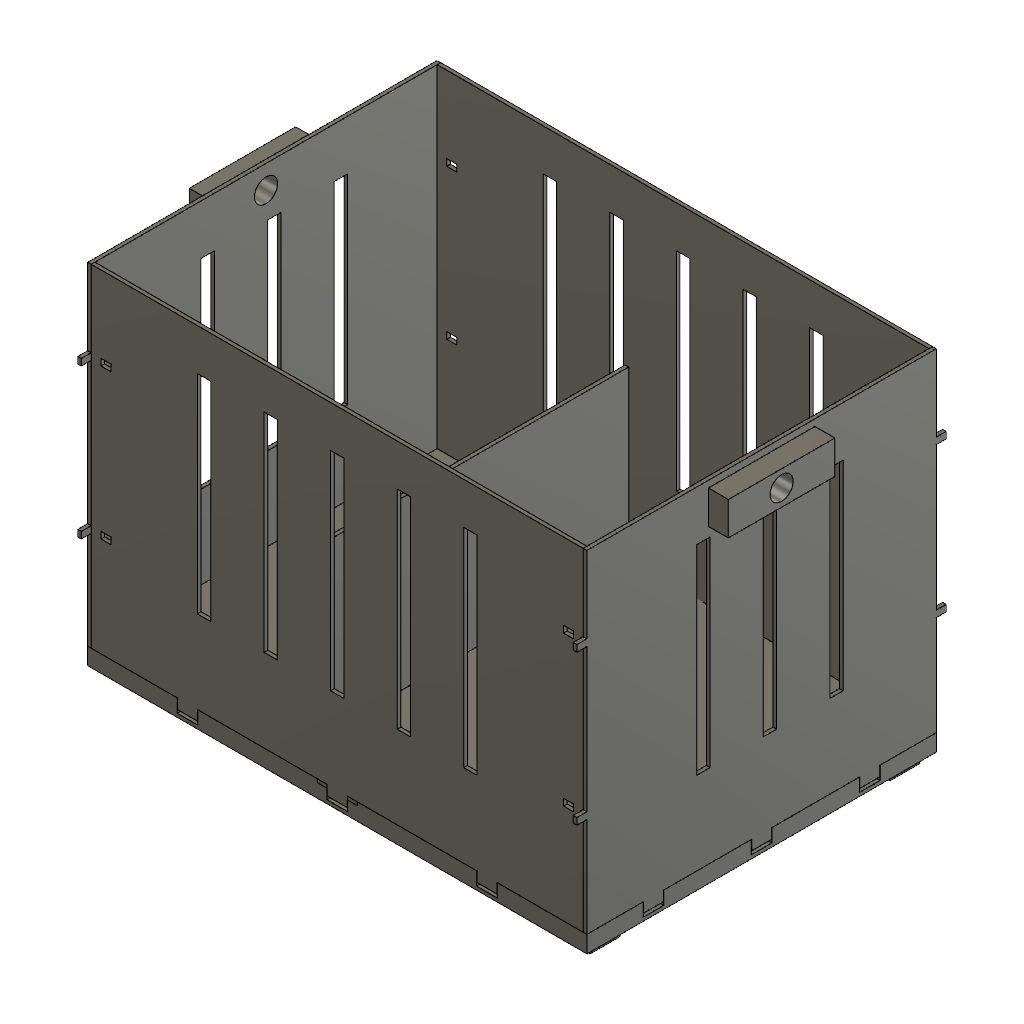
snapbox_5part (Autodesk Fusion 360 design; units mm, degrees)
part number: 2026-11-01-21-20-34-892
Autodesk Fusion 360 part; units mm, degrees
sketch "草图31" plane through (0, 0, 0) normal (0, 0, 1) x (1, 0, 0)
  line L0 (0, 0) -> (260, 0)
  line L1 (260, 0) -> (260, 180)
  line L2 (260, 180) -> (0, 180)
  line L3 (0, 180) -> (0, 0)
ref_plane "工作平面25" through (0, 0, 2.2) normal (0, 0, 1) x (1, 0, 0)
sketch "草图32" plane through (0, 0, 2.2) normal (0, 0, 1) x (1, 0, 0)
  line L0 (0, 0) -> (2.2, 0)
  line L1 (2.2, 0) -> (2.2, 180)
  line L2 (2.2, 180) -> (0, 180)
  line L3 (0, 180) -> (0, 0)
  line L4 (257.8, 0) -> (260, 0)
  line L5 (260, 0) -> (260, 180)
  line L6 (260, 180) -> (257.8, 180)
  line L7 (257.8, 180) -> (257.8, 0)
  line L8 (2.2, 0) -> (257.8, 0)
  line L9 (257.8, 0) -> (257.8, 2.2)
  line L10 (257.8, 2.2) -> (2.2, 2.2)
  line L11 (2.2, 2.2) -> (2.2, 0)
  line L12 (2.2, 177.8) -> (257.8, 177.8)
  line L13 (257.8, 177.8) -> (257.8, 180)
  line L14 (257.8, 180) -> (2.2, 180)
  line L15 (2.2, 180) -> (2.2, 177.8)
ref_plane "工作平面26" through (0, 0, -5) normal (0, 0, 1) x (1, 0, 0)
sketch "草图33" plane through (0, 0, -5) normal (0, 0, 1) x (1, 0, 0)
  line L0 (4, 6) -> (40, 6)
  line L1 (40, 6) -> (40, 24)
  line L2 (40, 24) -> (4, 24)
  line L3 (4, 24) -> (4, 6)
  line L4 (4, 156) -> (40, 156)
  line L5 (40, 156) -> (40, 174)
  line L6 (40, 174) -> (4, 174)
  line L7 (4, 174) -> (4, 156)
  line L8 (220, 6) -> (256, 6)
  line L9 (256, 6) -> (256, 24)
  line L10 (256, 24) -> (220, 24)
  line L11 (220, 24) -> (220, 6)
  line L12 (220, 156) -> (256, 156)
  line L13 (256, 156) -> (256, 174)
  line L14 (256, 174) -> (220, 174)
  line L15 (220, 174) -> (220, 156)
ref_plane "工作平面27" through (0, 0, 2.2) normal (0, 0, 1) x (1, 0, 0)
sketch "草图34" plane through (0, 0, 2.2) normal (0, 0, 1) x (1, 0, 0)
  line L0 (0, 23.8) -> (2.2, 23.8)
  line L1 (2.2, 23.8) -> (2.2, 36.2)
  line L2 (2.2, 36.2) -> (0, 36.2)
  line L3 (0, 36.2) -> (0, 23.8)
  line L4 (257.8, 23.8) -> (260, 23.8)
  line L5 (260, 23.8) -> (260, 36.2)
  line L6 (260, 36.2) -> (257.8, 36.2)
  line L7 (257.8, 36.2) -> (257.8, 23.8)
  line L8 (0, 83.8) -> (2.2, 83.8)
  line L9 (2.2, 83.8) -> (2.2, 96.2)
  line L10 (2.2, 96.2) -> (0, 96.2)
  line L11 (0, 96.2) -> (0, 83.8)
  line L12 (257.8, 83.8) -> (260, 83.8)
  line L13 (260, 83.8) -> (260, 96.2)
  line L14 (260, 96.2) -> (257.8, 96.2)
  line L15 (257.8, 96.2) -> (257.8, 83.8)
  line L16 (0, 143.8) -> (2.2, 143.8)
  line L17 (2.2, 143.8) -> (2.2, 156.2)
  line L18 (2.2, 156.2) -> (0, 156.2)
  line L19 (0, 156.2) -> (0, 143.8)
  line L20 (257.8, 143.8) -> (260, 143.8)
  line L21 (260, 143.8) -> (260, 156.2)
  line L22 (260, 156.2) -> (257.8, 156.2)
  line L23 (257.8, 156.2) -> (257.8, 143.8)
  line L24 (43.8, 0) -> (56.2, 0)
  line L25 (56.2, 0) -> (56.2, 2.2)
  line L26 (56.2, 2.2) -> (43.8, 2.2)
  line L27 (43.8, 2.2) -> (43.8, 0)
  line L28 (43.8, 177.8) -> (56.2, 177.8)
  line L29 (56.2, 177.8) -> (56.2, 180)
  line L30 (56.2, 180) -> (43.8, 180)
  line L31 (43.8, 180) -> (43.8, 177.8)
  line L32 (123.8, 0) -> (136.2, 0)
  line L33 (136.2, 0) -> (136.2, 2.2)
  line L34 (136.2, 2.2) -> (123.8, 2.2)
  line L35 (123.8, 2.2) -> (123.8, 0)
  line L36 (123.8, 177.8) -> (136.2, 177.8)
  line L37 (136.2, 177.8) -> (136.2, 180)
  line L38 (136.2, 180) -> (123.8, 180)
  line L39 (123.8, 180) -> (123.8, 177.8)
  line L40 (203.8, 0) -> (216.2, 0)
  line L41 (216.2, 0) -> (216.2, 2.2)
  line L42 (216.2, 2.2) -> (203.8, 2.2)
  line L43 (203.8, 2.2) -> (203.8, 0)
  line L44 (203.8, 177.8) -> (216.2, 177.8)
  line L45 (216.2, 177.8) -> (216.2, 180)
  line L46 (216.2, 180) -> (203.8, 180)
  line L47 (203.8, 180) -> (203.8, 177.8)
sketch "草图35" plane through (0, 0, 0) normal (1, 0, 0) x (0, 0, -1)
  line L0 (-10.2, 0) -> (-10.2, 180)
  line L1 (-10.2, 180) -> (-160, 180)
  line L2 (-160, 180) -> (-160, 0)
  line L3 (-160, 0) -> (-10.2, 0)
  line L4 (-4.2, 24) -> (-4.2, 36)
  line L5 (-4.2, 36) -> (-10.2, 36)
  line L6 (-10.2, 36) -> (-10.2, 24)
  line L7 (-10.2, 24) -> (-4.2, 24)
  line L8 (-4.2, 84) -> (-4.2, 96)
  line L9 (-4.2, 96) -> (-10.2, 96)
  line L10 (-10.2, 96) -> (-10.2, 84)
  line L11 (-10.2, 84) -> (-4.2, 84)
  line L12 (-4.2, 144) -> (-4.2, 156)
  line L13 (-4.2, 156) -> (-10.2, 156)
  line L14 (-10.2, 156) -> (-10.2, 144)
  line L15 (-10.2, 144) -> (-4.2, 144)
sketch "草图36" plane through (0, 0, 0) normal (1, 0, 0) x (0, 0, -1)
  line L0 (-48, -6) -> (-48, 1)
  line L1 (-48, 1) -> (-52, 1)
  line L2 (-52, 1) -> (-52, -6)
  line L3 (-52, -6) -> (-48, -6)
  line L4 (-48, 179) -> (-48, 186)
  line L5 (-48, 186) -> (-52, 186)
  line L6 (-52, 186) -> (-52, 179)
  line L7 (-52, 179) -> (-48, 179)
  line L8 (-118, -6) -> (-118, 1)
  line L9 (-118, 1) -> (-122, 1)
  line L10 (-122, 1) -> (-122, -6)
  line L11 (-122, -6) -> (-118, -6)
  line L12 (-118, 179) -> (-118, 186)
  line L13 (-118, 186) -> (-122, 186)
  line L14 (-122, 186) -> (-122, 179)
  line L15 (-122, 179) -> (-118, 179)
ref_plane "工作平面28" through (0, 0, 136) normal (0, 0, 1) x (1, 0, 0)
sketch "草图37" plane through (0, 0, 136) normal (0, 0, 1) x (1, 0, 0)
  line L0 (-12, 58) -> (1, 58)
  line L1 (1, 58) -> (1, 122)
  line L2 (1, 122) -> (-12, 122)
  line L3 (-12, 122) -> (-12, 58)
ref_plane "工作平面29" through (1.1, 0, 0) normal (1, 0, 0) x (0, 1, 0)
sketch "草图38" plane through (1.1, 0, 0) normal (1, 0, 0) x (0, 0, -1)
  circle A0 through (-138, 90, -1.1) (-148.5, 96.0622, -1.1) (-148.5, 83.9378, -1.1)
ref_plane "工作平面30" through (257.8, 0, 0) normal (1, 0, 0) x (0, 1, 0)
sketch "草图39" plane through (257.8, 0, 0) normal (1, 0, 0) x (0, 0, -1)
  line L0 (-10.2, 0) -> (-10.2, 180)
  line L1 (-10.2, 180) -> (-160, 180)
  line L2 (-160, 180) -> (-160, 0)
  line L3 (-160, 0) -> (-10.2, 0)
  line L4 (-4.2, 24) -> (-4.2, 36)
  line L5 (-4.2, 36) -> (-10.2, 36)
  line L6 (-10.2, 36) -> (-10.2, 24)
  line L7 (-10.2, 24) -> (-4.2, 24)
  line L8 (-4.2, 84) -> (-4.2, 96)
  line L9 (-4.2, 96) -> (-10.2, 96)
  line L10 (-10.2, 96) -> (-10.2, 84)
  line L11 (-10.2, 84) -> (-4.2, 84)
  line L12 (-4.2, 144) -> (-4.2, 156)
  line L13 (-4.2, 156) -> (-10.2, 156)
  line L14 (-10.2, 156) -> (-10.2, 144)
  line L15 (-10.2, 144) -> (-4.2, 144)
ref_plane "工作平面31" through (257.8, 0, 0) normal (1, 0, 0) x (0, 1, 0)
sketch "草图40" plane through (257.8, 0, 0) normal (1, 0, 0) x (0, 0, -1)
  line L0 (-48, -6) -> (-48, 1)
  line L1 (-48, 1) -> (-52, 1)
  line L2 (-52, 1) -> (-52, -6)
  line L3 (-52, -6) -> (-48, -6)
  line L4 (-48, 179) -> (-48, 186)
  line L5 (-48, 186) -> (-52, 186)
  line L6 (-52, 186) -> (-52, 179)
  line L7 (-52, 179) -> (-48, 179)
  line L8 (-118, -6) -> (-118, 1)
  line L9 (-118, 1) -> (-122, 1)
  line L10 (-122, 1) -> (-122, -6)
  line L11 (-122, -6) -> (-118, -6)
  line L12 (-118, 179) -> (-118, 186)
  line L13 (-118, 186) -> (-122, 186)
  line L14 (-122, 186) -> (-122, 179)
  line L15 (-122, 179) -> (-118, 179)
ref_plane "工作平面32" through (0, 0, 136) normal (0, 0, 1) x (1, 0, 0)
sketch "草图41" plane through (0, 0, 136) normal (0, 0, 1) x (1, 0, 0)
  line L0 (259, 58) -> (272, 58)
  line L1 (272, 58) -> (272, 122)
  line L2 (272, 122) -> (259, 122)
  line L3 (259, 122) -> (259, 58)
ref_plane "工作平面33" through (258.9, 0, 0) normal (1, 0, 0) x (0, 1, 0)
sketch "草图42" plane through (258.9, 0, 0) normal (1, 0, 0) x (0, 0, -1)
  circle A0 centre (-145, 90) radius 7
sketch "草图43" plane through (0, 0, 0) normal (0, 1, 0) x (1, 0, 0)
  line L0 (2.2, -10.2) -> (257.8, -10.2)
  line L1 (257.8, -10.2) -> (257.8, -160)
  line L2 (257.8, -160) -> (2.2, -160)
  line L3 (2.2, -160) -> (2.2, -10.2)
  line L4 (44, -4.2) -> (56, -4.2)
  line L5 (56, -4.2) -> (56, -10.2)
  line L6 (56, -10.2) -> (44, -10.2)
  line L7 (44, -10.2) -> (44, -4.2)
  line L8 (124, -4.2) -> (136, -4.2)
  line L9 (136, -4.2) -> (136, -10.2)
  line L10 (136, -10.2) -> (124, -10.2)
  line L11 (124, -10.2) -> (124, -4.2)
  line L12 (204, -4.2) -> (216, -4.2)
  line L13 (216, -4.2) -> (216, -10.2)
  line L14 (216, -10.2) -> (204, -10.2)
  line L15 (204, -10.2) -> (204, -4.2)
  line L16 (118, -8.2) -> (142, -8.2)
  line L17 (142, -8.2) -> (142, -10.5)
  line L18 (142, -10.5) -> (118, -10.5)
  line L19 (118, -10.5) -> (118, -8.2)
ref_plane "工作平面34" through (0, 1.1, 0) normal (0, 1, 0) x (0, 0, 1)
sketch "草图44" plane through (0, 1.1, 0) normal (0, 1, 0) x (1, 0, 0)
  line L0 (8, -48) -> (14, -48)
  line L1 (14, -48) -> (14, -52)
  line L2 (14, -52) -> (8, -52)
  line L3 (8, -52) -> (8, -48)
  line L4 (246, -48) -> (252, -48)
  line L5 (252, -48) -> (252, -52)
  line L6 (252, -52) -> (246, -52)
  line L7 (246, -52) -> (246, -48)
  line L8 (8, -118) -> (14, -118)
  line L9 (14, -118) -> (14, -122)
  line L10 (14, -122) -> (8, -122)
  line L11 (8, -122) -> (8, -118)
  line L12 (246, -118) -> (252, -118)
  line L13 (252, -118) -> (252, -122)
  line L14 (252, -122) -> (246, -122)
  line L15 (246, -122) -> (246, -118)
ref_plane "工作平面35" through (0, 177.8, 0) normal (0, 1, 0) x (0, 0, 1)
sketch "草图45" plane through (0, 177.8, 0) normal (0, 1, 0) x (1, 0, 0)
  line L0 (2.2, -10.2) -> (257.8, -10.2)
  line L1 (257.8, -10.2) -> (257.8, -160)
  line L2 (257.8, -160) -> (2.2, -160)
  line L3 (2.2, -160) -> (2.2, -10.2)
  line L4 (44, -4.2) -> (56, -4.2)
  line L5 (56, -4.2) -> (56, -10.2)
  line L6 (56, -10.2) -> (44, -10.2)
  line L7 (44, -10.2) -> (44, -4.2)
  line L8 (124, -4.2) -> (136, -4.2)
  line L9 (136, -4.2) -> (136, -10.2)
  line L10 (136, -10.2) -> (124, -10.2)
  line L11 (124, -10.2) -> (124, -4.2)
  line L12 (204, -4.2) -> (216, -4.2)
  line L13 (216, -4.2) -> (216, -10.2)
  line L14 (216, -10.2) -> (204, -10.2)
  line L15 (204, -10.2) -> (204, -4.2)
  line L16 (118, -8.2) -> (142, -8.2)
  line L17 (142, -8.2) -> (142, -10.5)
  line L18 (142, -10.5) -> (118, -10.5)
  line L19 (118, -10.5) -> (118, -8.2)
ref_plane "工作平面36" through (0, 178.9, 0) normal (0, 1, 0) x (0, 0, 1)
sketch "草图46" plane through (0, 178.9, 0) normal (0, 1, 0) x (1, 0, 0)
  line L0 (8, -48) -> (14, -48)
  line L1 (14, -48) -> (14, -52)
  line L2 (14, -52) -> (8, -52)
  line L3 (8, -52) -> (8, -48)
  line L4 (246, -48) -> (252, -48)
  line L5 (252, -48) -> (252, -52)
  line L6 (252, -52) -> (246, -52)
  line L7 (246, -52) -> (246, -48)
  line L8 (8, -118) -> (14, -118)
  line L9 (14, -118) -> (14, -122)
  line L10 (14, -122) -> (8, -122)
  line L11 (8, -122) -> (8, -118)
  line L12 (246, -118) -> (252, -118)
  line L13 (252, -118) -> (252, -122)
  line L14 (252, -122) -> (246, -122)
  line L15 (246, -122) -> (246, -118)
ref_plane "工作平面37" through (0, 178.9, 0) normal (0, 1, 0) x (0, 0, 1)
sketch "草图47" plane through (0, 178.9, 0) normal (0, 1, 0) x (1, 0, 0)
  line L0 (68, -122) -> (72, -122)
  line L1 (72, -122) -> (72, -150)
  line L2 (72, -150) -> (68, -150)
  line L3 (68, -150) -> (68, -122)
  line L4 (108, -122) -> (112, -122)
  line L5 (112, -122) -> (112, -150)
  line L6 (112, -150) -> (108, -150)
  line L7 (108, -150) -> (108, -122)
  line L8 (128, -122) -> (132, -122)
  line L9 (132, -122) -> (132, -150)
  line L10 (132, -150) -> (128, -150)
  line L11 (128, -150) -> (128, -122)
  line L12 (148, -122) -> (152, -122)
  line L13 (152, -122) -> (152, -150)
  line L14 (152, -150) -> (148, -150)
  line L15 (148, -150) -> (148, -122)
  line L16 (188, -122) -> (192, -122)
  line L17 (192, -122) -> (192, -150)
  line L18 (192, -150) -> (188, -150)
  line L19 (188, -150) -> (188, -122)
ref_plane "工作平面38" through (0, 178.9, 0) normal (0, 1, 0) x (0, 0, 1)
sketch "草图48" plane through (0, 178.9, 0) normal (0, 1, 0) x (1, 0, 0)
  line L0 (128, -155) -> (132, -155)
  line L1 (132, -155) -> (132, -163)
  line L2 (132, -163) -> (128, -163)
  line L3 (128, -163) -> (128, -155)
ref_plane "工作平面39" through (0, 177.8, 0) normal (0, 1, 0) x (0, 0, 1)
sketch "草图49" plane through (0, 177.8, 0) normal (0, 1, 0) x (1, 0, 0)
  line L0 (2.2, -10.2) -> (257.8, -10.2)
  line L1 (257.8, -10.2) -> (257.8, -160)
  line L2 (257.8, -160) -> (2.2, -160)
  line L3 (2.2, -160) -> (2.2, -10.2)
  line L4 (44, -4.2) -> (56, -4.2)
  line L5 (56, -4.2) -> (56, -10.2)
  line L6 (56, -10.2) -> (44, -10.2)
  line L7 (44, -10.2) -> (44, -4.2)
  line L8 (124, -4.2) -> (136, -4.2)
  line L9 (136, -4.2) -> (136, -10.2)
  line L10 (136, -10.2) -> (124, -10.2)
  line L11 (124, -10.2) -> (124, -4.2)
  line L12 (204, -4.2) -> (216, -4.2)
  line L13 (216, -4.2) -> (216, -10.2)
  line L14 (216, -10.2) -> (204, -10.2)
  line L15 (204, -10.2) -> (204, -4.2)
  line L16 (118, -8.2) -> (142, -8.2)
  line L17 (142, -8.2) -> (142, -10.5)
  line L18 (142, -10.5) -> (118, -10.5)
  line L19 (118, -10.5) -> (118, -8.2)
ref_plane "工作平面40" through (0, 178.9, 0) normal (0, 1, 0) x (0, 0, 1)
sketch "草图50" plane through (0, 178.9, 0) normal (0, 1, 0) x (1, 0, 0)
  line L0 (8, -48) -> (14, -48)
  line L1 (14, -48) -> (14, -52)
  line L2 (14, -52) -> (8, -52)
  line L3 (8, -52) -> (8, -48)
  line L4 (246, -48) -> (252, -48)
  line L5 (252, -48) -> (252, -52)
  line L6 (252, -52) -> (246, -52)
  line L7 (246, -52) -> (246, -48)
  line L8 (8, -118) -> (14, -118)
  line L9 (14, -118) -> (14, -122)
  line L10 (14, -122) -> (8, -122)
  line L11 (8, -122) -> (8, -118)
  line L12 (246, -118) -> (252, -118)
  line L13 (252, -118) -> (252, -122)
  line L14 (252, -122) -> (246, -122)
  line L15 (246, -122) -> (246, -118)
sketch "草图51" plane through (0, 0, 0) normal (0, 0, 1) x (1, 0, 0)
  line L0 (0, 0) -> (300, 0)
  line L1 (300, 0) -> (300, 210)
  line L2 (300, 210) -> (0, 210)
  line L3 (0, 210) -> (0, 0)
extrude "01_底板_260x180x2.2" add sketch "草图51" along normal blind 2.2 makes body 1
ref_plane "工作平面41" through (0, 0, 2.2) normal (0, 0, 1) x (1, 0, 0)
sketch "草图52" plane through (0, 0, 2.2) normal (0, 0, 1) x (1, 0, 0)
  line L0 (0, 0) -> (2.2, 0)
  line L1 (2.2, 0) -> (2.2, 210)
  line L2 (2.2, 210) -> (0, 210)
  line L3 (0, 210) -> (0, 0)
  line L4 (297.8, 0) -> (300, 0)
  line L5 (300, 0) -> (300, 210)
  line L6 (300, 210) -> (297.8, 210)
  line L7 (297.8, 210) -> (297.8, 0)
  line L8 (2.2, 0) -> (297.8, 0)
  line L9 (297.8, 0) -> (297.8, 2.2)
  line L10 (297.8, 2.2) -> (2.2, 2.2)
  line L11 (2.2, 2.2) -> (2.2, 0)
  line L12 (2.2, 207.8) -> (297.8, 207.8)
  line L13 (297.8, 207.8) -> (297.8, 210)
  line L14 (297.8, 210) -> (2.2, 210)
  line L15 (2.2, 210) -> (2.2, 207.8)
extrude "01_四周承榫沿_高8mm" add sketch "草图52" along normal blind 8 bodies 1
ref_plane "工作平面42" through (0, 0, -5) normal (0, 0, 1) x (1, 0, 0)
sketch "草图53" plane through (0, 0, -5) normal (0, 0, 1) x (1, 0, 0)
  line L0 (4, 6) -> (40, 6)
  line L1 (40, 6) -> (40, 24)
  line L2 (40, 24) -> (4, 24)
  line L3 (4, 24) -> (4, 6)
  line L4 (4, 186) -> (40, 186)
  line L5 (40, 186) -> (40, 204)
  line L6 (40, 204) -> (4, 204)
  line L7 (4, 204) -> (4, 186)
  line L8 (260, 6) -> (296, 6)
  line L9 (296, 6) -> (296, 24)
  line L10 (296, 24) -> (260, 24)
  line L11 (260, 24) -> (260, 6)
  line L12 (260, 186) -> (296, 186)
  line L13 (296, 186) -> (296, 204)
  line L14 (296, 204) -> (260, 204)
  line L15 (260, 204) -> (260, 186)
extrude "01_支撑脚_高5mm" add sketch "草图53" along normal blind 5 bodies 1
ref_plane "工作平面43" through (0, 0, 2.2) normal (0, 0, 1) x (1, 0, 0)
sketch "草图54" plane through (0, 0, 2.2) normal (0, 0, 1) x (1, 0, 0)
  line L0 (0, 33.8) -> (2.2, 33.8)
  line L1 (2.2, 33.8) -> (2.2, 46.2)
  line L2 (2.2, 46.2) -> (0, 46.2)
  line L3 (0, 46.2) -> (0, 33.8)
  line L4 (297.8, 33.8) -> (300, 33.8)
  line L5 (300, 33.8) -> (300, 46.2)
  line L6 (300, 46.2) -> (297.8, 46.2)
  line L7 (297.8, 46.2) -> (297.8, 33.8)
  line L8 (0, 98.8) -> (2.2, 98.8)
  line L9 (2.2, 98.8) -> (2.2, 111.2)
  line L10 (2.2, 111.2) -> (0, 111.2)
  line L11 (0, 111.2) -> (0, 98.8)
  line L12 (297.8, 98.8) -> (300, 98.8)
  line L13 (300, 98.8) -> (300, 111.2)
  line L14 (300, 111.2) -> (297.8, 111.2)
  line L15 (297.8, 111.2) -> (297.8, 98.8)
  line L16 (0, 163.8) -> (2.2, 163.8)
  line L17 (2.2, 163.8) -> (2.2, 176.2)
  line L18 (2.2, 176.2) -> (0, 176.2)
  line L19 (0, 176.2) -> (0, 163.8)
  line L20 (297.8, 163.8) -> (300, 163.8)
  line L21 (300, 163.8) -> (300, 176.2)
  line L22 (300, 176.2) -> (297.8, 176.2)
  line L23 (297.8, 176.2) -> (297.8, 163.8)
  line L24 (53.8, 0) -> (66.2, 0)
  line L25 (66.2, 0) -> (66.2, 2.2)
  line L26 (66.2, 2.2) -> (53.8, 2.2)
  line L27 (53.8, 2.2) -> (53.8, 0)
  line L28 (53.8, 207.8) -> (66.2, 207.8)
  line L29 (66.2, 207.8) -> (66.2, 210)
  line L30 (66.2, 210) -> (53.8, 210)
  line L31 (53.8, 210) -> (53.8, 207.8)
  line L32 (143.8, 0) -> (156.2, 0)
  line L33 (156.2, 0) -> (156.2, 2.2)
  line L34 (156.2, 2.2) -> (143.8, 2.2)
  line L35 (143.8, 2.2) -> (143.8, 0)
  line L36 (143.8, 207.8) -> (156.2, 207.8)
  line L37 (156.2, 207.8) -> (156.2, 210)
  line L38 (156.2, 210) -> (143.8, 210)
  line L39 (143.8, 210) -> (143.8, 207.8)
  line L40 (233.8, 0) -> (246.2, 0)
  line L41 (246.2, 0) -> (246.2, 2.2)
  line L42 (246.2, 2.2) -> (233.8, 2.2)
  line L43 (233.8, 2.2) -> (233.8, 0)
  line L44 (233.8, 207.8) -> (246.2, 207.8)
  line L45 (246.2, 207.8) -> (246.2, 210)
  line L46 (246.2, 210) -> (233.8, 210)
  line L47 (233.8, 210) -> (233.8, 207.8)
extrude "01_承榫沿榫槽_12个_深8mm" cut sketch "草图54" along normal blind 8 bodies 1
sketch "草图55" plane through (0, 0, 0) normal (1, 0, 0) x (0, 0, -1)
  line L0 (-10.2, 0) -> (-10.2, 210)
  line L1 (-10.2, 210) -> (-210, 210)
  line L2 (-210, 210) -> (-210, 0)
  line L3 (-210, 0) -> (-10.2, 0)
  line L4 (-4.2, 34) -> (-4.2, 46)
  line L5 (-4.2, 46) -> (-10.2, 46)
  line L6 (-10.2, 46) -> (-10.2, 34)
  line L7 (-10.2, 34) -> (-4.2, 34)
  line L8 (-4.2, 99) -> (-4.2, 111)
  line L9 (-4.2, 111) -> (-10.2, 111)
  line L10 (-10.2, 111) -> (-10.2, 99)
  line L11 (-10.2, 99) -> (-4.2, 99)
  line L12 (-4.2, 164) -> (-4.2, 176)
  line L13 (-4.2, 176) -> (-10.2, 176)
  line L14 (-10.2, 176) -> (-10.2, 164)
  line L15 (-10.2, 164) -> (-4.2, 164)
extrude "02_左侧板主体+底榫" add sketch "草图55" along normal blind 2.2 separate body makes body 2
sketch "草图56" plane through (0, 0, 0) normal (1, 0, 0) x (0, 0, -1)
  line L0 (-70, -6) -> (-70, 1)
  line L1 (-70, 1) -> (-74, 1)
  line L2 (-74, 1) -> (-74, -6)
  line L3 (-74, -6) -> (-70, -6)
  line L4 (-70, 209) -> (-70, 216)
  line L5 (-70, 216) -> (-74, 216)
  line L6 (-74, 216) -> (-74, 209)
  line L7 (-74, 209) -> (-70, 209)
  line L8 (-160, -6) -> (-160, 1)
  line L9 (-160, 1) -> (-164, 1)
  line L10 (-164, 1) -> (-164, -6)
  line L11 (-164, -6) -> (-160, -6)
  line L12 (-160, 209) -> (-160, 216)
  line L13 (-160, 216) -> (-164, 216)
  line L14 (-164, 216) -> (-164, 209)
  line L15 (-164, 209) -> (-160, 209)
extrude "02_左侧板弹性卡钩_4个" add sketch "草图56" along normal blind 2.2 bodies 2
ref_plane "工作平面44" through (0, 0, 186) normal (0, 0, 1) x (1, 0, 0)
sketch "草图57" plane through (0, 0, 186) normal (0, 0, 1) x (1, 0, 0)
  line L0 (-12, 73) -> (1, 73)
  line L1 (1, 73) -> (1, 137)
  line L2 (1, 137) -> (-12, 137)
  line L3 (-12, 137) -> (-12, 73)
extrude "02_拎榫法兰" add sketch "草图57" along normal blind 20 bodies 2
ref_plane "工作平面45" through (1.1, 0, 0) normal (1, 0, 0) x (0, 1, 0)
sketch "草图58" plane through (1.1, 0, 0) normal (1, 0, 0) x (0, 0, -1)
  circle A0 through (-189, 105, -1.1) (-199.5, 111.0622, -1.1) (-199.5, 98.9378, -1.1)
extrude "02_拎榫贯通孔_r7" cut sketch "草图58" along normal blind 16 and the other way blind 16 contours A0 in plane through (0, 0, 0) normal (1, 0, 0) bodies 2
ref_plane "工作平面46" through (297.8, 0, 0) normal (1, 0, 0) x (0, 1, 0)
sketch "草图59" plane through (297.8, 0, 0) normal (1, 0, 0) x (0, 0, -1)
  line L0 (-10.2, 0) -> (-10.2, 210)
  line L1 (-10.2, 210) -> (-210, 210)
  line L2 (-210, 210) -> (-210, 0)
  line L3 (-210, 0) -> (-10.2, 0)
  line L4 (-4.2, 34) -> (-4.2, 46)
  line L5 (-4.2, 46) -> (-10.2, 46)
  line L6 (-10.2, 46) -> (-10.2, 34)
  line L7 (-10.2, 34) -> (-4.2, 34)
  line L8 (-4.2, 99) -> (-4.2, 111)
  line L9 (-4.2, 111) -> (-10.2, 111)
  line L10 (-10.2, 111) -> (-10.2, 99)
  line L11 (-10.2, 99) -> (-4.2, 99)
  line L12 (-4.2, 164) -> (-4.2, 176)
  line L13 (-4.2, 176) -> (-10.2, 176)
  line L14 (-10.2, 176) -> (-10.2, 164)
  line L15 (-10.2, 164) -> (-4.2, 164)
extrude "03_右侧板主体+底榫" add sketch "草图59" along normal blind 2.2 separate body makes body 3
ref_plane "工作平面47" through (297.8, 0, 0) normal (1, 0, 0) x (0, 1, 0)
sketch "草图60" plane through (297.8, 0, 0) normal (1, 0, 0) x (0, 0, -1)
  line L0 (-70, -6) -> (-70, 1)
  line L1 (-70, 1) -> (-74, 1)
  line L2 (-74, 1) -> (-74, -6)
  line L3 (-74, -6) -> (-70, -6)
  line L4 (-70, 209) -> (-70, 216)
  line L5 (-70, 216) -> (-74, 216)
  line L6 (-74, 216) -> (-74, 209)
  line L7 (-74, 209) -> (-70, 209)
  line L8 (-160, -6) -> (-160, 1)
  line L9 (-160, 1) -> (-164, 1)
  line L10 (-164, 1) -> (-164, -6)
  line L11 (-164, -6) -> (-160, -6)
  line L12 (-160, 209) -> (-160, 216)
  line L13 (-160, 216) -> (-164, 216)
  line L14 (-164, 216) -> (-164, 209)
  line L15 (-164, 209) -> (-160, 209)
extrude "03_右侧板弹性卡钩_4个" add sketch "草图60" along normal blind 2.2 bodies 3
ref_plane "工作平面48" through (0, 0, 186) normal (0, 0, 1) x (1, 0, 0)
sketch "草图61" plane through (0, 0, 186) normal (0, 0, 1) x (1, 0, 0)
  line L0 (299, 73) -> (312, 73)
  line L1 (312, 73) -> (312, 137)
  line L2 (312, 137) -> (299, 137)
  line L3 (299, 137) -> (299, 73)
extrude "03_拎榫法兰" add sketch "草图61" along normal blind 20 bodies 3
ref_plane "工作平面49" through (298.9, 0, 0) normal (1, 0, 0) x (0, 1, 0)
sketch "草图62" plane through (298.9, 0, 0) normal (1, 0, 0) x (0, 0, -1)
  circle A0 centre (-196, 105) radius 7
extrude "03_拎榫贯通孔_r7" cut sketch "草图62" along normal blind 16 and the other way blind 16 bodies 3
sketch "草图63" plane through (0, 0, 0) normal (0, 1, 0) x (1, 0, 0)
  line L0 (2.2, -10.2) -> (297.8, -10.2)
  line L1 (297.8, -10.2) -> (297.8, -210)
  line L2 (297.8, -210) -> (2.2, -210)
  line L3 (2.2, -210) -> (2.2, -10.2)
  line L4 (54, -4.2) -> (66, -4.2)
  line L5 (66, -4.2) -> (66, -10.2)
  line L6 (66, -10.2) -> (54, -10.2)
  line L7 (54, -10.2) -> (54, -4.2)
  line L8 (144, -4.2) -> (156, -4.2)
  line L9 (156, -4.2) -> (156, -10.2)
  line L10 (156, -10.2) -> (144, -10.2)
  line L11 (144, -10.2) -> (144, -4.2)
  line L12 (234, -4.2) -> (246, -4.2)
  line L13 (246, -4.2) -> (246, -10.2)
  line L14 (246, -10.2) -> (234, -10.2)
  line L15 (234, -10.2) -> (234, -4.2)
  line L16 (138, -8.2) -> (162, -8.2)
  line L17 (162, -8.2) -> (162, -10.5)
  line L18 (162, -10.5) -> (138, -10.5)
  line L19 (138, -10.5) -> (138, -8.2)
extrude "04_前盖板主体+底榫+推入卡紧" add sketch "草图63" along normal blind 2.2 separate body makes body 4
ref_plane "工作平面50" through (0, 1.1, 0) normal (0, 1, 0) x (0, 0, 1)
sketch "草图64" plane through (0, 1.1, 0) normal (0, 1, 0) x (1, 0, 0)
  line L0 (8, -70) -> (14, -70)
  line L1 (14, -70) -> (14, -74)
  line L2 (14, -74) -> (8, -74)
  line L3 (8, -74) -> (8, -70)
  line L4 (286, -70) -> (292, -70)
  line L5 (292, -70) -> (292, -74)
  line L6 (292, -74) -> (286, -74)
  line L7 (286, -74) -> (286, -70)
  line L8 (8, -160) -> (14, -160)
  line L9 (14, -160) -> (14, -164)
  line L10 (14, -164) -> (8, -164)
  line L11 (8, -164) -> (8, -160)
  line L12 (286, -160) -> (292, -160)
  line L13 (292, -160) -> (292, -164)
  line L14 (292, -164) -> (286, -164)
  line L15 (286, -164) -> (286, -160)
extrude "04_固定卡槽_4个" cut sketch "草图64" along normal blind 2.5 and the other way blind 2.5 bodies 4
ref_plane "工作平面51" through (0, 207.8, 0) normal (0, 1, 0) x (0, 0, 1)
sketch "草图65" plane through (0, 207.8, 0) normal (0, 1, 0) x (1, 0, 0)
  line L0 (2.2, -10.2) -> (297.8, -10.2)
  line L1 (297.8, -10.2) -> (297.8, -210)
  line L2 (297.8, -210) -> (2.2, -210)
  line L3 (2.2, -210) -> (2.2, -10.2)
  line L4 (54, -4.2) -> (66, -4.2)
  line L5 (66, -4.2) -> (66, -10.2)
  line L6 (66, -10.2) -> (54, -10.2)
  line L7 (54, -10.2) -> (54, -4.2)
  line L8 (144, -4.2) -> (156, -4.2)
  line L9 (156, -4.2) -> (156, -10.2)
  line L10 (156, -10.2) -> (144, -10.2)
  line L11 (144, -10.2) -> (144, -4.2)
  line L12 (234, -4.2) -> (246, -4.2)
  line L13 (246, -4.2) -> (246, -10.2)
  line L14 (246, -10.2) -> (234, -10.2)
  line L15 (234, -10.2) -> (234, -4.2)
  line L16 (138, -8.2) -> (162, -8.2)
  line L17 (162, -8.2) -> (162, -10.5)
  line L18 (162, -10.5) -> (138, -10.5)
  line L19 (138, -10.5) -> (138, -8.2)
extrude "05_后盖板主体+底榫+插入卡紧" add sketch "草图65" along normal blind 2.2 separate body makes body 5
ref_plane "工作平面52" through (0, 208.9, 0) normal (0, 1, 0) x (0, 0, 1)
sketch "草图66" plane through (0, 208.9, 0) normal (0, 1, 0) x (1, 0, 0)
  line L0 (8, -70) -> (14, -70)
  line L1 (14, -70) -> (14, -74)
  line L2 (14, -74) -> (8, -74)
  line L3 (8, -74) -> (8, -70)
  line L4 (286, -70) -> (292, -70)
  line L5 (292, -70) -> (292, -74)
  line L6 (292, -74) -> (286, -74)
  line L7 (286, -74) -> (286, -70)
  line L8 (8, -160) -> (14, -160)
  line L9 (14, -160) -> (14, -164)
  line L10 (14, -164) -> (8, -164)
  line L11 (8, -164) -> (8, -160)
  line L12 (286, -160) -> (292, -160)
  line L13 (292, -160) -> (292, -164)
  line L14 (292, -164) -> (286, -164)
  line L15 (286, -164) -> (286, -160)
extrude "05_固定卡槽_4个" cut sketch "草图66" along normal blind 2.5 and the other way blind 2.5 bodies 5
move_body "移动17" bodies 2 to x (1, 0, 0) y (0, 1, 0) z (0, 0, 1) at (-60, 0, 0)
move_body "移动18" bodies 3 to x (1, 0, 0) y (0, 1, 0) z (0, 0, 1) at (60, 0, 0)
move_body "移动19" bodies 4 to x (1, 0, 0) y (0, 1, 0) z (0, 0, 1) at (0, -60, 0)
move_body "移动20" bodies 5 to x (1, 0, 0) y (0, 1, 0) z (0, 0, 1) at (0, 60, 0)
move_body "移动21" bodies 2 to x (1, 0, 0) y (0, 1, 0) z (0, 0, 1) at (60, 0, 0)
move_body "移动22" bodies 3 to x (1, 0, 0) y (0, 1, 0) z (0, 0, 1) at (-60, 0, 0)
move_body "移动23" bodies 4 to x (1, 0, 0) y (0, 1, 0) z (0, 0, 1) at (0, 60, 0)
move_body "移动24" bodies 5 to x (1, 0, 0) y (0, 1, 0) z (0, 0, 1) at (0, -60, 0)
ref_plane "工作平面53" through (0, 1.1, 0) normal (0, 1, 0) x (0, 0, 1)
sketch "草图67" plane through (0, 1.1, 0) normal (0, 1, 0) x (1, 0, 0)
  line L0 (66, -60) -> (74, -60)
  line L1 (74, -60) -> (74, -185)
  line L2 (74, -185) -> (66, -185)
  line L3 (66, -185) -> (66, -60)
  line L4 (106, -60) -> (114, -60)
  line L5 (114, -60) -> (114, -185)
  line L6 (114, -185) -> (106, -185)
  line L7 (106, -185) -> (106, -60)
  line L8 (146, -60) -> (154, -60)
  line L9 (154, -60) -> (154, -185)
  line L10 (154, -185) -> (146, -185)
  line L11 (146, -185) -> (146, -60)
  line L12 (186, -60) -> (194, -60)
  line L13 (194, -60) -> (194, -185)
  line L14 (194, -185) -> (186, -185)
  line L15 (186, -185) -> (186, -60)
  line L16 (226, -60) -> (234, -60)
  line L17 (234, -60) -> (234, -185)
  line L18 (234, -185) -> (226, -185)
  line L19 (226, -185) -> (226, -60)
extrude "07_04_前盖板散热格栅_5条" cut sketch "草图67" along normal blind 2.5 and the other way blind 2.5 bodies 4
ref_plane "工作平面54" through (0, 208.9, 0) normal (0, 1, 0) x (0, 0, 1)
sketch "草图68" plane through (0, 208.9, 0) normal (0, 1, 0) x (1, 0, 0)
  line L0 (66, -60) -> (74, -60)
  line L1 (74, -60) -> (74, -185)
  line L2 (74, -185) -> (66, -185)
  line L3 (66, -185) -> (66, -60)
  line L4 (106, -60) -> (114, -60)
  line L5 (114, -60) -> (114, -185)
  line L6 (114, -185) -> (106, -185)
  line L7 (106, -185) -> (106, -60)
  line L8 (146, -60) -> (154, -60)
  line L9 (154, -60) -> (154, -185)
  line L10 (154, -185) -> (146, -185)
  line L11 (146, -185) -> (146, -60)
  line L12 (186, -60) -> (194, -60)
  line L13 (194, -60) -> (194, -185)
  line L14 (194, -185) -> (186, -185)
  line L15 (186, -185) -> (186, -60)
  line L16 (226, -60) -> (234, -60)
  line L17 (234, -60) -> (234, -185)
  line L18 (234, -185) -> (226, -185)
  line L19 (226, -185) -> (226, -60)
extrude "07_05_后盖板散热格栅_5条" cut sketch "草图68" along normal blind 2.5 and the other way blind 2.5 bodies 5
ref_plane "工作平面55" through (1.1, 0, 0) normal (1, 0, 0) x (0, 1, 0)
sketch "草图69" plane through (1.1, 0, 0) normal (1, 0, 0) x (0, 0, -1)
  line L0 (-60, 66) -> (-60, 74)
  line L1 (-60, 74) -> (-180, 74)
  line L2 (-180, 74) -> (-180, 66)
  line L3 (-180, 66) -> (-60, 66)
  line L4 (-60, 106) -> (-60, 114)
  line L5 (-60, 114) -> (-180, 114)
  line L6 (-180, 114) -> (-180, 106)
  line L7 (-180, 106) -> (-60, 106)
  line L8 (-60, 146) -> (-60, 154)
  line L9 (-60, 154) -> (-180, 154)
  line L10 (-180, 154) -> (-180, 146)
  line L11 (-180, 146) -> (-60, 146)
extrude "07_02_左侧板散热格栅_3条" cut sketch "草图69" along normal blind 3 and the other way blind 3 bodies 2
ref_plane "工作平面56" through (298.9, 0, 0) normal (1, 0, 0) x (0, 1, 0)
sketch "草图70" plane through (298.9, 0, 0) normal (1, 0, 0) x (0, 0, -1)
  line L0 (-60, 66) -> (-60, 74)
  line L1 (-60, 74) -> (-180, 74)
  line L2 (-180, 74) -> (-180, 66)
  line L3 (-180, 66) -> (-60, 66)
  line L4 (-60, 106) -> (-60, 114)
  line L5 (-60, 114) -> (-180, 114)
  line L6 (-180, 114) -> (-180, 106)
  line L7 (-180, 106) -> (-60, 106)
  line L8 (-60, 146) -> (-60, 154)
  line L9 (-60, 154) -> (-180, 154)
  line L10 (-180, 154) -> (-180, 146)
  line L11 (-180, 146) -> (-60, 146)
extrude "07_03_右侧板散热格栅_3条" cut sketch "草图70" along normal blind 3 and the other way blind 3 bodies 3
move_body "移动25" bodies 2 to x (1, 0, 0) y (0, 1, 0) z (0, 0, 1) at (-60, 0, 0)
move_body "移动26" bodies 3 to x (1, 0, 0) y (0, 1, 0) z (0, 0, 1) at (60, 0, 0)
move_body "移动27" bodies 4 to x (1, 0, 0) y (0, 1, 0) z (0, 0, 1) at (0, -60, 0)
move_body "移动28" bodies 5 to x (1, 0, 0) y (0, 1, 0) z (0, 0, 1) at (0, 60, 0)
move_body "移动29" bodies 2 to x (1, 0, 0) y (0, 1, 0) z (0, 0, 1) at (60, 0, 0)
move_body "移动30" bodies 3 to x (1, 0, 0) y (0, 1, 0) z (0, 0, 1) at (-60, 0, 0)
move_body "移动31" bodies 4 to x (1, 0, 0) y (0, 1, 0) z (0, 0, 1) at (0, 60, 0)
move_body "移动32" bodies 5 to x (1, 0, 0) y (0, 1, 0) z (0, 0, 1) at (0, -60, 0)
ref_plane "工作平面57" through (115.1, 0, 0) normal (1, 0, 0) x (0, 1, 0)
sketch "草图71" plane through (115.1, 0, 0) normal (1, 0, 0) x (0, 0, -1)
  line L0 (-10.2, 2.2) -> (-10.2, 207.8)
  line L1 (-10.2, 207.8) -> (-110.2, 207.8)
  line L2 (-110.2, 207.8) -> (-110.2, 2.2)
  line L3 (-110.2, 2.2) -> (-10.2, 2.2)
extrude "08_左右分隔板_半高100" add sketch "草图71" along normal blind 2.2 separate body makes body 6
ref_plane "工作平面58" through (115.1, 0, 0) normal (1, 0, 0) x (0, 1, 0)
sketch "草图72" plane through (115.1, 0, 0) normal (1, 0, 0) x (0, 0, -1)
  line L0 (-10.2, 2.2) -> (-10.2, 207.8)
  line L1 (-10.2, 207.8) -> (-110.2, 207.8)
  line L2 (-110.2, 207.8) -> (-110.2, 2.2)
  line L3 (-110.2, 2.2) -> (-10.2, 2.2)
move_body "移动33" bodies 2 to x (1, 0, 0) y (0, 1, 0) z (0, 0, 1) at (-60, 0, 0)
move_body "移动34" bodies 3 to x (1, 0, 0) y (0, 1, 0) z (0, 0, 1) at (60, 0, 0)
move_body "移动35" bodies 4 to x (1, 0, 0) y (0, 1, 0) z (0, 0, 1) at (0, -60, 0)
move_body "移动36" bodies 5 to x (1, 0, 0) y (0, 1, 0) z (0, 0, 1) at (0, 60, 0)
move_body "移动37" bodies 6 to x (1, 0, 0) y (0, 1, 0) z (0, 0, 1) at (0, 0, 60)
move_body "移动38" bodies 2 to x (1, 0, 0) y (0, 1, 0) z (0, 0, 1) at (60, 0, 0)
move_body "移动39" bodies 3 to x (1, 0, 0) y (0, 1, 0) z (0, 0, 1) at (-60, 0, 0)
move_body "移动40" bodies 4 to x (1, 0, 0) y (0, 1, 0) z (0, 0, 1) at (0, 60, 0)
move_body "移动41" bodies 5 to x (1, 0, 0) y (0, 1, 0) z (0, 0, 1) at (0, -60, 0)
move_body "移动42" bodies 6 to x (1, 0, 0) y (0, 1, 0) z (0, 0, 1) at (0, 0, -60)
move_body "移动43" bodies 1 2 3 4 5 6 to x (1, 0, 0) y (0, 0, -1) z (0, 1, 0) at (0, 0, 0)
named bodies: "01_底座总成", "02_左侧板", "03_右侧板", "04_前盖板", "05_后盖板", "07_左右分隔板"
